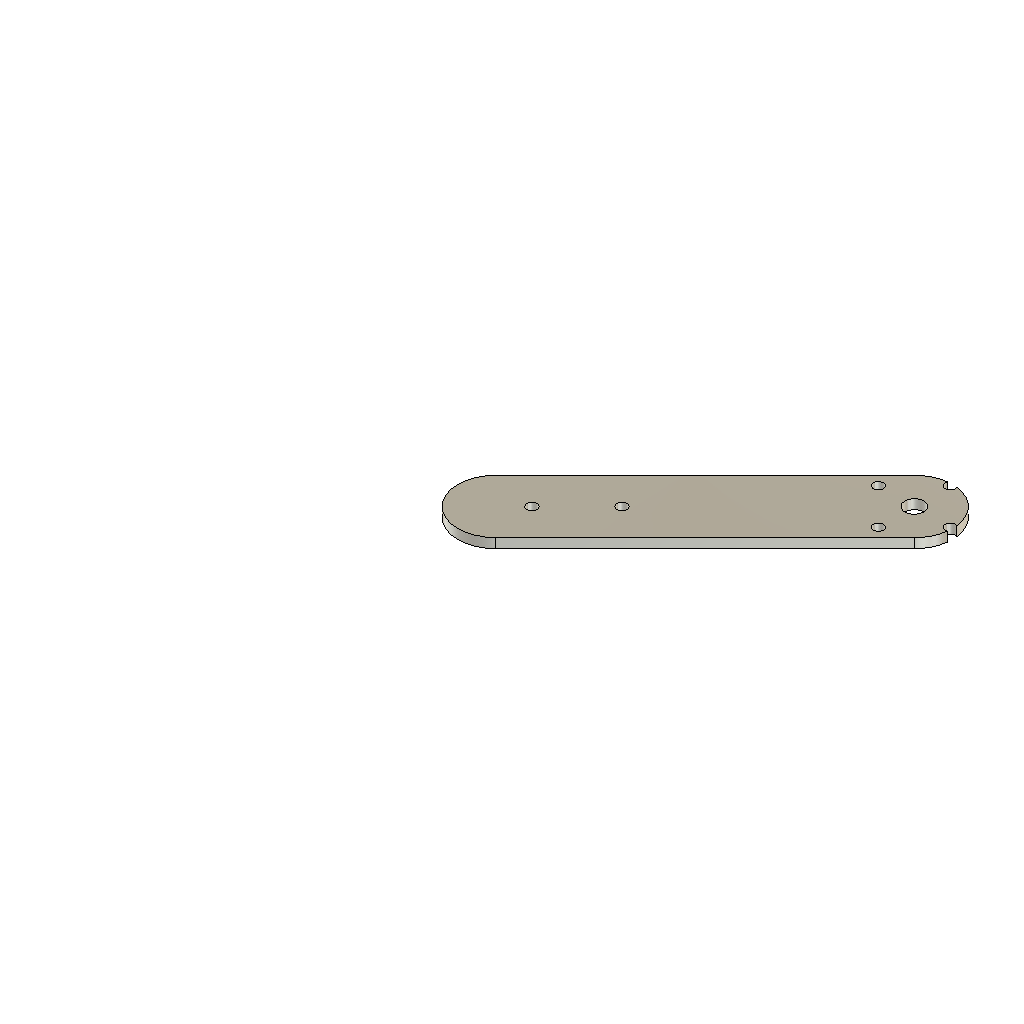
Arm_1 (Autodesk Fusion 360 design; units mm, degrees)
part number: 2026-10-25-14-10-35-427
Autodesk Fusion 360 part; units mm, degrees
sketch "Sketch1" plane through (0, 0, 6) normal (0, 0, 1) x (1, 0, 0)
  line L0 (79.9031, 96.8736) -> (14.1421, 31.1127)
  arc A0 (14.1421, 31.1127) -> (31.1127, 14.1421) centre (22.6274, 22.6274) ccw
  line L1 (31.1127, 14.1421) -> (96.8736, 79.9031)
  arc A1 (96.8736, 79.9031) -> (79.9031, 96.8736) centre (88.3883, 88.3883) ccw
  circle A2 centre (88.39, 77.08) radius 1.6
  circle A3 centre (88.39, 99.7) radius 1.6
  circle A4 centre (42.43, 42.43) radius 1.6
  circle A5 centre (28.28, 28.28) radius 1.6
  line L2 (0, 0) -> (88.3883, 88.3883) construction
  line L3 (0, 0) -> (125, 0) construction
  circle A6 centre (99.7, 88.39) radius 1.6 construction
  circle A7 centre (77.08, 88.39) radius 1.6 construction
  circle A8 centre (88.39, 88.39) radius 3 construction
  circle A9 centre (99.7, 88.39) radius 1.6
  circle A10 centre (77.08, 88.39) radius 1.6
  circle A11 centre (88.3883, 88.3883) radius 3
  dimension "d69" = 24
  dimension "d83" = 125
  dimension "d84" = 45
  dimension "d85" = 32
  dimension "d86" = 28.28
  dimension "d87" = 28.28
  dimension "d88" = 42.43
  dimension "d89" = 42.43
  dimension "d90" = 77.08
  dimension "d91" = 88.39
  dimension "d92" = 125
  dimension "d93" = 99.7
  dimension "d94" = 88.39
  dimension "d95" = 3.2
  dimension "d96" = 3.2
  dimension "d97" = 88.39
  dimension "d98" = 77.08
  dimension "d99" = 88.39
  dimension "d100" = 99.7
  dimension "d101" = 6
  dimension "d102" = 88.39
  dimension "d103" = 88.39
  dimension "d104" = 3.2
  dimension "d105" = 3.2
  dimension "d106" = 6
  constraint tangent L0 A0
  constraint tangent A0 L1
  constraint parallel L0 L1
  constraint tangent L1 A1
  constraint tangent L0 A1
  constraint horizontal L3
  constraint coincident L2.start L3.start
  constraint coincident A1.centre L2
  constraint coincident A0.centre L2
  constraint concentric A6 A9
  constraint concentric A7 A10
  constraint coincident A1.centre L2.end
  measures "d69" diameter of A0
  measures "d83" distance of L2.start A1.centre
  measures "d84" angle of L2 L3
  measures "d85" distance of L2.start A0.centre
  measures "d86" vertical distance of L2.start A5.centre
  measures "d87" horizontal distance of L2.start A5.centre
  measures "d88" horizontal distance of L2.start A4.centre
  measures "d89" vertical distance of L2.start A4.centre
  measures "d90" vertical distance of L2.start A2.centre
  measures "d91" horizontal distance of L2.start A2.centre
  measures "d92" distance of L2.start A1.centre
  measures "d93" vertical distance of L2.start A3.centre
  measures "d94" horizontal distance of L2.start A3.centre
  measures "d95" diameter of A6
  measures "d96" diameter of A7
  measures "d97" vertical distance of L2.start A7.centre
  measures "d98" horizontal distance of L2.start A7.centre
  measures "d99" vertical distance of L2.start A6.centre
  measures "d100" horizontal distance of L2.start A6.centre
  measures "d101" diameter of A8
  measures "d102" vertical distance of L2.start A8.centre
  measures "d103" horizontal distance of L2.start A8.centre
  measures "d104" diameter of A9
  measures "d105" diameter of A10
  measures "d106" diameter of A11
extrude "Extrude1" add sketch "Sketch1" along normal blind 3 contours L0 A0 L1 A1 A3 A9
equation "d69 = ArmW"
equation "d95 = HoleM3"
equation "d96 = HoleM3"
equation "d104 = HoleM3"
equation "d105 = HoleM3"
equation "d107 = ArmT"
equation "ArmW = 24 mm"
equation "ArmT = 3 mm"
equation "HoleM3 = 3.2 mm"
named bodies: "Arm1"
